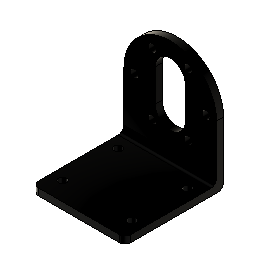
MM-JGB37 (Autodesk Fusion 360 design; units mm, degrees)
Autodesk Fusion 360 part; units mm, degrees
sketch "Sketch1" plane through (0, 0, 0) normal (0, 0, 1) x (1, 0, 0)
  line L0 (0, 0) -> (40, 0)
  line L1 (40, 0) -> (40, 42.5)
  line L2 (40, 42.5) -> (0, 42.5)
  line L3 (0, 42.5) -> (0, 0)
  circle A0 centre (5, 32) radius 1.75
  circle A1 centre (35, 32) radius 1.75
  line L4 (5, 32) -> (35, 32) construction
  line L5 (5, 32) -> (5, 8) construction
  circle A2 centre (5, 8) radius 1.75
  line L6 (35, 32) -> (35, 8) construction
  circle A3 centre (35, 8) radius 1.75
  line L7 (5, 8) -> (35, 8) construction
  line L8 (0, 39.5) -> (40, 39.5)
  dimension "d1" = 40
  dimension "d2" = 42.5
  dimension "d3" = 3.5
  dimension "d6" = 3.5
  dimension "d7" = 3.5
  dimension "d8" = 24
  dimension "d9" = 8
  dimension "d10" = 3.5
  dimension "d11" = 30
  dimension "d12" = 5
  dimension "d13" = 3
  constraint horizontal L0
  constraint vertical L1
  constraint horizontal L2
  constraint vertical L3
  constraint coincident L0.start L3.end
  constraint coincident A0.centre L4.start
  constraint coincident A1.centre L4.end
  constraint perpendicular L3 L4
  constraint perpendicular L4 L5
  constraint coincident L5.end A2.centre
  constraint perpendicular L4 L6
  constraint equal L5 L6
  constraint coincident L6.end A3.centre
  constraint coincident L3 L8.start
  constraint coincident L1 L8.end
  constraint perpendicular L1 L8
  measures "d1" distance of L0.start L0.end
  measures "d2" distance of L0.start L2.end
  measures "d3" diameter of A0
  measures "d6" diameter of A1
  measures "d7" diameter of A2
  measures "d8" distance of A0.centre L5.end
  measures "d9" distance of L0 L5.end
  measures "d10" diameter of A3
  measures "d11" distance of L5.end L6.end
  measures "d12" distance of L3 L5.end
  measures "d13" distance of L2 L8
extrude "Extrude1" add sketch "Sketch1" along normal blind 3 contours L0 L1 L3 L8
extrude "Extrude2" add sketch "Sketch1" along normal blind 47 contours L1 L2 L3 L8
sketch "Sketch2" plane through (0, 39.5, 0) normal (0, -1, 0) x (1, 0, 0)
  line L0 (0, 3) -> (40, 3)
  line L1 (40, 3) -> (40, 47)
  line L2 (40, 47) -> (0, 47)
  line L3 (0, 47) -> (0, 3)
  circle A0 centre (20, 27) radius 20
  line L4 (0, 27) -> (40, 27) construction
  circle A1 centre (20, 27) radius 15.5 construction
  circle A2 centre (4.5, 27) radius 1.75
  line L5 (0, 3) -> (40, 3)
  circle A3 centre (12.25, 13.5766) radius 1.75
  circle A4 centre (27.75, 13.5766) radius 1.75
  circle A5 centre (35.5, 27) radius 1.75
  circle A6 centre (27.75, 40.4234) radius 1.75
  circle A7 centre (12.25, 40.4234) radius 1.75
  line L6 (20, 42.5) -> (20, 11.5) construction
  line L7 (0, 0) -> (40, 0)
  line L8 (13.5, 34) -> (13.5, 20)
  line L9 (26.5, 34) -> (26.5, 20)
  line L10 (13.5, 34) -> (26.5, 34) construction
  line L11 (13.5, 20) -> (26.5, 20) construction
  arc A8 (13.5, 20) -> (26.5, 20) centre (20, 20) ccw
  arc A9 (26.5, 34) -> (13.5, 34) centre (20, 34) ccw
  dimension "d18" = 40
  dimension "d19" = 31
  dimension "d20" = 3.5
  dimension "d22" = 360
  dimension "d23" = 13
  dimension "d24" = 13
  dimension "d25" = 20
  dimension "d26" = 34
  constraint tangent L2 A0
  constraint coincident A0 L4.start
  constraint coincident A0 L4.end
  constraint coincident L1 L4.end
  constraint concentric A0 A1
  constraint tangent L1 A0
  constraint coincident A1 A2.centre
  constraint coincident L4 A2.centre
  constraint parallel L4 L5
  constraint coincident A1 L6.start
  constraint coincident A1 L6.end
  constraint perpendicular L4 L6
  constraint coincident A0.centre L6
  constraint coincident L6 A9.centre
  constraint coincident L6 A8.centre
  constraint tangent L8 A8
  constraint tangent L8 A9
  constraint tangent L9 A8
  constraint tangent L9 A9
  measures "d18" diameter of A0
  measures "d19" diameter of A1
  measures "d20" diameter of A2
  measures "d23" diameter of A9
  measures "d24" diameter of A8
  measures "d25" distance of A8.centre L7
  measures "d26" distance of A9.centre L7
extrude "Extrude3" cut sketch "Sketch2" against normal blind 3 contours L2 L3 A0 | L1 L2 A0 | A2 | A3 | A4 | A5 | A6 | A7 | L8 L9 A8 A9
fillet "Fillet1" radius 2.5 1 edges at (20, 42.5, 0)
fillet "Fillet2" radius 2.5 2 edges at (0, 0, 1.5) (40, 0, 1.5)
fillet "Fillet3" radius 2.5 1 edges at (20, 39.5, 3)
equation "d6 = d3"
equation "d7 = d3"
equation "d10 = d3"
